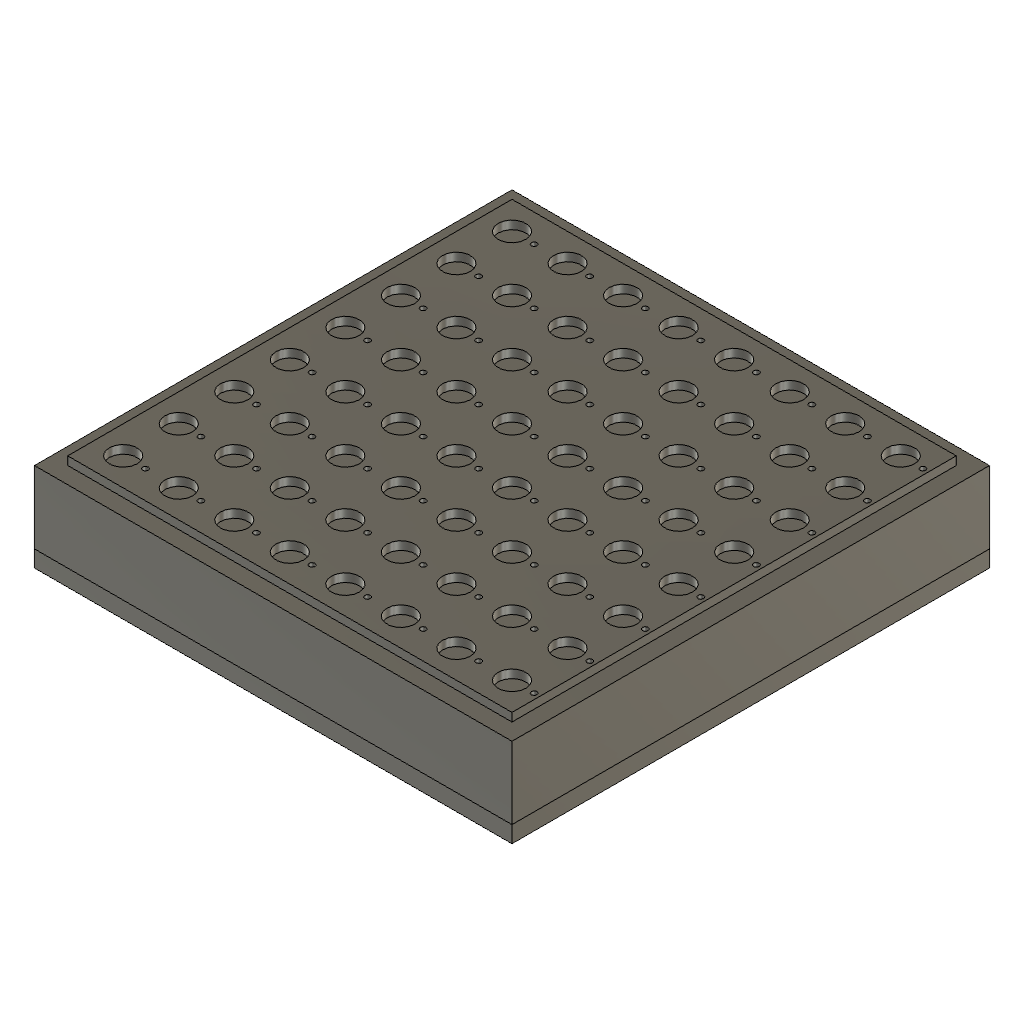
final (Autodesk Fusion 360 design; units mm, degrees)
part number: 2026-11-04-18-17-43-096
part number: 2026-11-04-18-49-42-338
part number: 2026-11-04-20-15-32-787
Autodesk Fusion 360 part; units mm, degrees
sketch "Sketch1" plane through (0, 0, 0) normal (0, 0, 1) x (1, 0, 0)
  circle A0 centre (5, -5) radius 2.5
  circle A1 centre (15, -5) radius 2.5
  circle A2 centre (25, -5) radius 2.5
  circle A3 centre (35, -5) radius 2.5
  circle A4 centre (45, -5) radius 2.5
  circle A5 centre (55, -5) radius 2.5
  circle A6 centre (65, -5) radius 2.5
  circle A7 centre (75, -5) radius 2.5
  circle A8 centre (5, -15) radius 2.5
  circle A9 centre (15, -15) radius 2.5
  circle A10 centre (25, -15) radius 2.5
  circle A11 centre (35, -15) radius 2.5
  circle A12 centre (45, -15) radius 2.5
  circle A13 centre (55, -15) radius 2.5
  circle A14 centre (65, -15) radius 2.5
  circle A15 centre (75, -15) radius 2.5
  circle A16 centre (5, -25) radius 2.5
  circle A17 centre (15, -25) radius 2.5
  circle A18 centre (25, -25) radius 2.5
  circle A19 centre (35, -25) radius 2.5
  circle A20 centre (45, -25) radius 2.5
  circle A21 centre (55, -25) radius 2.5
  circle A22 centre (65, -25) radius 2.5
  circle A23 centre (75, -25) radius 2.5
  circle A24 centre (5, -35) radius 2.5
  circle A25 centre (15, -35) radius 2.5
  circle A26 centre (25, -35) radius 2.5
  circle A27 centre (35, -35) radius 2.5
  circle A28 centre (45, -35) radius 2.5
  circle A29 centre (55, -35) radius 2.5
  circle A30 centre (65, -35) radius 2.5
  circle A31 centre (75, -35) radius 2.5
  circle A32 centre (5, -45) radius 2.5
  circle A33 centre (15, -45) radius 2.5
  circle A34 centre (25, -45) radius 2.5
  circle A35 centre (35, -45) radius 2.5
  circle A36 centre (45, -45) radius 2.5
  circle A37 centre (55, -45) radius 2.5
  circle A38 centre (65, -45) radius 2.5
  circle A39 centre (75, -45) radius 2.5
  circle A40 centre (5, -55) radius 2.5
  circle A41 centre (15, -55) radius 2.5
  circle A42 centre (25, -55) radius 2.5
  circle A43 centre (35, -55) radius 2.5
  circle A44 centre (45, -55) radius 2.5
  circle A45 centre (55, -55) radius 2.5
  circle A46 centre (65, -55) radius 2.5
  circle A47 centre (75, -55) radius 2.5
  circle A48 centre (5, -65) radius 2.5
  circle A49 centre (15, -65) radius 2.5
  circle A50 centre (25, -65) radius 2.5
  circle A51 centre (35, -65) radius 2.5
  circle A52 centre (45, -65) radius 2.5
  circle A53 centre (55, -65) radius 2.5
  circle A54 centre (65, -65) radius 2.5
  circle A55 centre (75, -65) radius 2.5
  circle A56 centre (5, -75) radius 2.5
  circle A57 centre (15, -75) radius 2.5
  circle A58 centre (25, -75) radius 2.5
  circle A59 centre (35, -75) radius 2.5
  circle A60 centre (45, -75) radius 2.5
  circle A61 centre (55, -75) radius 2.5
  circle A62 centre (65, -75) radius 2.5
  circle A63 centre (75, -75) radius 2.5
  line L0 (80, -75) -> (80, -80)
  line L1 (80, -80) -> (75, -80)
  line L2 (80, -80) -> (0, -80)
  line L3 (0, -80) -> (0, 0)
  line L4 (0, 0) -> (80, 0)
  line L5 (80, 0) -> (80, -80)
  dimension "d3" = 5
  dimension "d8" = 70
  dimension "d9" = -70
  dimension "d10" = 5
  dimension "d11" = 5
  constraint vertical L0
  constraint horizontal L1
  constraint horizontal L2
  constraint vertical L3
  constraint horizontal L4
  constraint vertical L5
  constraint coincident L3.end L4.start
  measures "d3" diameter of A0
  measures "d10" distance of A63.centre L0.start
  measures "d11" distance of A63.centre L1.end
extrude "Extrude1" add sketch "Sketch1" against normal blind 3 makes body 1
extrude "Extrude2" cut 1 faces at (18.9442, -68.9001, -3) along direction (0, 0, 1) blind 1.5 on bodies 1 bodies 1
sketch "Sketch1 (2)" plane through (0, 0, -1.5) normal (0, 0, -1) x (1, 0, 0) in component "mainbody "
  circle A0 centre (15, 15) radius 2.5
  circle A1 centre (35, 65) radius 2.5
  circle A2 centre (55, 55) radius 2.5
  circle A3 centre (35, 35) radius 2.5
  circle A4 centre (75, 25) radius 2.5
  circle A5 centre (55, 25) radius 2.5
  circle A6 centre (65, 15) radius 2.5
  circle A7 centre (25, 55) radius 2.5
  circle A8 centre (15, 55) radius 2.5
  circle A9 centre (75, 45) radius 2.5
  circle A10 centre (15, 25) radius 2.5
  circle A11 centre (5, 75) radius 2.5
  circle A12 centre (65, 65) radius 2.5
  circle A13 centre (25, 75) radius 2.5
  circle A14 centre (25, 65) radius 2.5
  circle A15 centre (55, 75) radius 2.5
  circle A16 centre (75, 75) radius 2.5
  circle A17 centre (65, 35) radius 2.5
  circle A18 centre (25, 5) radius 2.5
  circle A19 centre (15, 35) radius 2.5
  circle A20 centre (45, 15) radius 2.5
  circle A21 centre (35, 5) radius 2.5
  circle A22 centre (35, 15) radius 2.5
  circle A23 centre (15, 5) radius 2.5
  circle A24 centre (65, 45) radius 2.5
  circle A25 centre (5, 45) radius 2.5
  circle A26 centre (75, 65) radius 2.5
  circle A27 centre (55, 35) radius 2.5
  line L0 (0, 0) -> (80, 0)
  line L1 (80, 0) -> (80, 80)
  line L2 (80, 80) -> (0, 80)
  line L3 (0, 80) -> (0, 0)
  circle A28 centre (65, 5) radius 2.5
  circle A29 centre (25, 15) radius 2.5
  circle A30 centre (15, 45) radius 2.5
  circle A31 centre (35, 25) radius 2.5
  circle A32 centre (45, 5) radius 2.5
  circle A33 centre (55, 15) radius 2.5
  circle A34 centre (65, 25) radius 2.5
  circle A35 centre (45, 45) radius 2.5
  circle A36 centre (5, 15) radius 2.5
  circle A37 centre (75, 55) radius 2.5
  circle A38 centre (75, 15) radius 2.5
  circle A39 centre (25, 25) radius 2.5
  circle A40 centre (25, 45) radius 2.5
  circle A41 centre (5, 55) radius 2.5
  circle A42 centre (25, 35) radius 2.5
  circle A43 centre (55, 45) radius 2.5
  circle A44 centre (45, 25) radius 2.5
  circle A45 centre (35, 75) radius 2.5
  circle A46 centre (15, 65) radius 2.5
  circle A47 centre (45, 65) radius 2.5
  circle A48 centre (5, 65) radius 2.5
  circle A49 centre (65, 75) radius 2.5
  circle A50 centre (15, 75) radius 2.5
  circle A51 centre (35, 55) radius 2.5
  circle A52 centre (75, 5) radius 2.5
  circle A53 centre (55, 5) radius 2.5
  circle A54 centre (5, 25) radius 2.5
  circle A55 centre (55, 65) radius 2.5
  circle A56 centre (5, 5) radius 2.5
  circle A57 centre (75, 35) radius 2.5
  circle A58 centre (45, 75) radius 2.5
  circle A59 centre (45, 35) radius 2.5
  circle A60 centre (5, 35) radius 2.5
  circle A61 centre (65, 55) radius 2.5
  circle A62 centre (45, 55) radius 2.5
  circle A63 centre (35, 45) radius 2.5
  line L4 (0, 0) -> (0, 80)
  circle A64 centre (5, 65) radius 2.5
  circle A65 centre (5, 75) radius 2.5
  circle A66 centre (15, 75) radius 2.5
  line L5 (0, 80) -> (80, 80)
  circle A67 centre (25, 75) radius 2.5
  circle A68 centre (35, 75) radius 2.5
  circle A69 centre (45, 75) radius 2.5
  circle A70 centre (55, 75) radius 2.5
  circle A71 centre (65, 75) radius 2.5
  circle A72 centre (75, 75) radius 2.5
  line L6 (80, 80) -> (80, 0)
  circle A73 centre (75, 65) radius 2.5
  circle A74 centre (65, 65) radius 2.5
  circle A75 centre (55, 65) radius 2.5
  circle A76 centre (45, 65) radius 2.5
  circle A77 centre (35, 65) radius 2.5
  circle A78 centre (25, 65) radius 2.5
  circle A79 centre (15, 65) radius 2.5
  circle A80 centre (5, 55) radius 2.5
  circle A81 centre (15, 55) radius 2.5
  circle A82 centre (25, 55) radius 2.5
  circle A83 centre (35, 55) radius 2.5
  circle A84 centre (45, 55) radius 2.5
  circle A85 centre (55, 55) radius 2.5
  circle A86 centre (65, 55) radius 2.5
  circle A87 centre (75, 55) radius 2.5
  circle A88 centre (75, 45) radius 2.5
  circle A89 centre (65, 45) radius 2.5
  circle A90 centre (55, 45) radius 2.5
  circle A91 centre (45, 45) radius 2.5
  circle A92 centre (35, 45) radius 2.5
  circle A93 centre (25, 45) radius 2.5
  circle A94 centre (15, 45) radius 2.5
  circle A95 centre (5, 45) radius 2.5
  circle A96 centre (5, 35) radius 2.5
  circle A97 centre (15, 35) radius 2.5
  circle A98 centre (25, 35) radius 2.5
  circle A99 centre (35, 35) radius 2.5
  circle A100 centre (45, 35) radius 2.5
  circle A101 centre (55, 35) radius 2.5
  circle A102 centre (65, 35) radius 2.5
  circle A103 centre (75, 35) radius 2.5
  circle A104 centre (75, 25) radius 2.5
  circle A105 centre (65, 25) radius 2.5
  circle A106 centre (55, 25) radius 2.5
  circle A107 centre (45, 25) radius 2.5
  circle A108 centre (35, 25) radius 2.5
  circle A109 centre (25, 25) radius 2.5
  circle A110 centre (15, 25) radius 2.5
  circle A111 centre (5, 25) radius 2.5
  circle A112 centre (5, 15) radius 2.5
  circle A113 centre (5, 5) radius 2.5
  line L7 (80, 0) -> (0, 0)
  circle A114 centre (15, 5) radius 2.5
  circle A115 centre (15, 15) radius 2.5
  circle A116 centre (25, 15) radius 2.5
  circle A117 centre (25, 5) radius 2.5
  circle A118 centre (35, 5) radius 2.5
  circle A119 centre (35, 15) radius 2.5
  circle A120 centre (45, 15) radius 2.5
  circle A121 centre (45, 5) radius 2.5
  circle A122 centre (55, 5) radius 2.5
  circle A123 centre (65, 5) radius 2.5
  circle A124 centre (75, 5) radius 2.5
  circle A125 centre (75, 15) radius 2.5
  circle A126 centre (65, 15) radius 2.5
  circle A127 centre (9, 75) radius 0.5
  line L8 (15, 75) -> (19, 75)
  circle A128 centre (19, 75) radius 0.5
  circle A129 centre (29, 75) radius 0.5
  circle A130 centre (39, 75) radius 0.5
  circle A131 centre (49, 75) radius 0.5
  circle A132 centre (59, 75) radius 0.5
  circle A133 centre (69, 75) radius 0.5
  circle A134 centre (79, 75) radius 0.5
  circle A135 centre (9, 65) radius 0.5
  circle A136 centre (19, 65) radius 0.5
  circle A137 centre (29, 65) radius 0.5
  circle A138 centre (39, 65) radius 0.5
  circle A139 centre (49, 65) radius 0.5
  circle A140 centre (59, 65) radius 0.5
  circle A141 centre (69, 65) radius 0.5
  circle A142 centre (79, 65) radius 0.5
  circle A143 centre (9, 55) radius 0.5
  circle A144 centre (19, 55) radius 0.5
  circle A145 centre (29, 55) radius 0.5
  circle A146 centre (39, 55) radius 0.5
  circle A147 centre (49, 55) radius 0.5
  circle A148 centre (59, 55) radius 0.5
  circle A149 centre (69, 55) radius 0.5
  circle A150 centre (79, 55) radius 0.5
  circle A151 centre (9, 45) radius 0.5
  circle A152 centre (19, 45) radius 0.5
  circle A153 centre (29, 45) radius 0.5
  circle A154 centre (39, 45) radius 0.5
  circle A155 centre (49, 45) radius 0.5
  circle A156 centre (59, 45) radius 0.5
  circle A157 centre (69, 45) radius 0.5
  circle A158 centre (79, 45) radius 0.5
  circle A159 centre (9, 35) radius 0.5
  circle A160 centre (19, 35) radius 0.5
  circle A161 centre (29, 35) radius 0.5
  circle A162 centre (39, 35) radius 0.5
  circle A163 centre (49, 35) radius 0.5
  circle A164 centre (59, 35) radius 0.5
  circle A165 centre (69, 35) radius 0.5
  circle A166 centre (79, 35) radius 0.5
  circle A167 centre (9, 25) radius 0.5
  circle A168 centre (19, 25) radius 0.5
  circle A169 centre (29, 25) radius 0.5
  circle A170 centre (39, 25) radius 0.5
  circle A171 centre (49, 25) radius 0.5
  circle A172 centre (59, 25) radius 0.5
  circle A173 centre (69, 25) radius 0.5
  circle A174 centre (79, 25) radius 0.5
  circle A175 centre (9, 15) radius 0.5
  circle A176 centre (19, 15) radius 0.5
  circle A177 centre (29, 15) radius 0.5
  circle A178 centre (39, 15) radius 0.5
  circle A179 centre (49, 15) radius 0.5
  circle A180 centre (59, 15) radius 0.5
  circle A181 centre (69, 15) radius 0.5
  circle A182 centre (79, 15) radius 0.5
  circle A183 centre (9, 5) radius 0.5
  circle A184 centre (19, 5) radius 0.5
  circle A185 centre (29, 5) radius 0.5
  circle A186 centre (39, 5) radius 0.5
  circle A187 centre (49, 5) radius 0.5
  circle A188 centre (59, 5) radius 0.5
  circle A189 centre (69, 5) radius 0.5
  circle A190 centre (79, 5) radius 0.5
  point P0 (72.5, 5)
  dimension "d20" = 4
  dimension "d21" = 1
  dimension "d22" = 4
  dimension "d26" = 70
  dimension "d27" = -70
  constraint coincident A50.centre A66.centre
  constraint horizontal L8
  measures "d20" distance of A11.centre A127.centre
  measures "d21" diameter of A127
  measures "d22" distance of A50.centre L8.end
extrude "Extrude1'" add sketch "Sketch1 (2)" along normal blind 3 separate body contours A0 A115 | A1 A77 | A2 A85 | A3 A99 | A4 A104 | A5 A106 | A6 A126 | A7 A82 | A8 A81 | A9 A88 | A10 A110 | A11 A65 | A12 A74 | A13 A67 | A14 A78 | A15 A70 | A16 A72 | A17 A102 | A18 A117 | A19 A97 | A20 A120 | A21 A118 | A22 A119 | A23 A114 | A24 A89 | A25 A95 | A26 A73 | A27 A101 | L0 L1 L2 L3 L4 L5 L6 L7 | A28 A123 | A29 A116 | A30 A94 | A31 A108 | A32 A121 | A33 | A34 A105 | A35 A91 | A36 A112 | A37 A87 | A38 A125 | A39 A109 | A40 A93 | A41 A80 | A42 A98 | A43 A90 | A44 A107 | A45 A68 | A46 A79 | A47 A76 | A48 A64 | A49 A71 | A50 A66 | A51 A83 | A52 A124 | A53 A122 | A54 A111 | A55 A75 | A56 A113 | A57 A103 | A58 A69 | A59 A100 | A60 A96 | A61 A86 | A62 A84 | A63 A92 makes body 2 in component "mainbody "
sketch "Sketch2" plane through (0, 0, 0) normal (0, 0, 1) x (-1, 0, 0)
  circle A0 centre (-15, 15) radius 2.5
  circle A1 centre (-35, 65) radius 2.5
  circle A2 centre (-55, 55) radius 2.5
  circle A3 centre (-35, 35) radius 2.5
  circle A4 centre (-75, 25) radius 2.5
  circle A5 centre (-55, 25) radius 2.5
  circle A6 centre (-65, 15) radius 2.5
  circle A7 centre (-25, 55) radius 2.5
  circle A8 centre (-15, 55) radius 2.5
  circle A9 centre (-75, 45) radius 2.5
  circle A10 centre (-15, 25) radius 2.5
  circle A11 centre (-5, 75) radius 2.5
  circle A12 centre (-65, 65) radius 2.5
  circle A13 centre (-25, 75) radius 2.5
  circle A14 centre (-25, 65) radius 2.5
  circle A15 centre (-55, 75) radius 2.5
  circle A16 centre (-75, 75) radius 2.5
  circle A17 centre (-65, 35) radius 2.5
  circle A18 centre (-25, 5) radius 2.5
  circle A19 centre (-15, 35) radius 2.5
  circle A20 centre (-45, 15) radius 2.5
  circle A21 centre (-35, 5) radius 2.5
  circle A22 centre (-35, 15) radius 2.5
  circle A23 centre (-15, 5) radius 2.5
  circle A24 centre (-65, 45) radius 2.5
  circle A25 centre (-5, 45) radius 2.5
  circle A26 centre (-75, 65) radius 2.5
  circle A27 centre (-55, 35) radius 2.5
  line L0 (-80, 0) -> (0, 0)
  line L1 (0, 0) -> (0, 80)
  line L2 (0, 80) -> (-80, 80)
  line L3 (-80, 80) -> (-80, 0)
  circle A28 centre (-65, 5) radius 2.5
  circle A29 centre (-25, 15) radius 2.5
  circle A30 centre (-15, 45) radius 2.5
  circle A31 centre (-35, 25) radius 2.5
  circle A32 centre (-45, 5) radius 2.5
  circle A33 centre (-55, 15) radius 2.5
  circle A34 centre (-65, 25) radius 2.5
  circle A35 centre (-45, 45) radius 2.5
  circle A36 centre (-5, 15) radius 2.5
  circle A37 centre (-75, 55) radius 2.5
  circle A38 centre (-75, 15) radius 2.5
  circle A39 centre (-25, 25) radius 2.5
  circle A40 centre (-25, 45) radius 2.5
  circle A41 centre (-5, 55) radius 2.5
  circle A42 centre (-25, 35) radius 2.5
  circle A43 centre (-55, 45) radius 2.5
  circle A44 centre (-45, 25) radius 2.5
  circle A45 centre (-35, 75) radius 2.5
  circle A46 centre (-15, 65) radius 2.5
  circle A47 centre (-45, 65) radius 2.5
  circle A48 centre (-5, 65) radius 2.5
  circle A49 centre (-65, 75) radius 2.5
  circle A50 centre (-15, 75) radius 2.5
  circle A51 centre (-35, 55) radius 2.5
  circle A52 centre (-75, 5) radius 2.5
  circle A53 centre (-55, 5) radius 2.5
  circle A54 centre (-5, 25) radius 2.5
  circle A55 centre (-55, 65) radius 2.5
  circle A56 centre (-5, 5) radius 2.5
  circle A57 centre (-75, 35) radius 2.5
  circle A58 centre (-45, 75) radius 2.5
  circle A59 centre (-45, 35) radius 2.5
  circle A60 centre (-5, 35) radius 2.5
  circle A61 centre (-65, 55) radius 2.5
  circle A62 centre (-45, 55) radius 2.5
  circle A63 centre (-35, 45) radius 2.5
  circle A64 centre (-9, 5) radius 0.5
  circle A65 centre (-9, 25) radius 0.5
  circle A66 centre (-9, 35) radius 0.5
  circle A67 centre (-9, 45) radius 0.5
  circle A68 centre (-9, 55) radius 0.5
  circle A69 centre (-9, 65) radius 0.5
  circle A70 centre (-9, 75) radius 0.5
  circle A71 centre (-9, 15) radius 0.5
  circle A72 centre (-19, 5) radius 0.5
  circle A73 centre (-19, 15) radius 0.5
  circle A74 centre (-19, 25) radius 0.5
  circle A75 centre (-19, 35) radius 0.5
  circle A76 centre (-19, 45) radius 0.5
  circle A77 centre (-19, 55) radius 0.5
  circle A78 centre (-19, 65) radius 0.5
  circle A79 centre (-19, 75) radius 0.5
  circle A80 centre (-29, 75) radius 0.5
  circle A81 centre (-29, 65) radius 0.5
  circle A82 centre (-29, 55) radius 0.5
  circle A83 centre (-29, 45) radius 0.5
  circle A84 centre (-29, 35) radius 0.5
  circle A85 centre (-29, 25) radius 0.5
  circle A86 centre (-29, 15) radius 0.5
  circle A87 centre (-29, 5) radius 0.5
  circle A88 centre (-39, 5) radius 0.5
  circle A89 centre (-39, 15) radius 0.5
  circle A90 centre (-39, 25) radius 0.5
  circle A91 centre (-39, 35) radius 0.5
  circle A92 centre (-39, 45) radius 0.5
  circle A93 centre (-39, 55) radius 0.5
  circle A94 centre (-39, 65) radius 0.5
  circle A95 centre (-39, 75) radius 0.5
  circle A96 centre (-49, 75) radius 0.5
  circle A97 centre (-49, 65) radius 0.5
  circle A98 centre (-49, 55) radius 0.5
  circle A99 centre (-49, 45) radius 0.5
  circle A100 centre (-49, 35) radius 0.5
  circle A101 centre (-49, 25) radius 0.5
  circle A102 centre (-49, 15) radius 0.5
  circle A103 centre (-49, 5) radius 0.5
  circle A104 centre (-59, 5) radius 0.5
  circle A105 centre (-59, 15) radius 0.5
  circle A106 centre (-59, 25) radius 0.5
  circle A107 centre (-59, 35) radius 0.5
  circle A108 centre (-59, 45) radius 0.5
  circle A109 centre (-59, 55) radius 0.5
  circle A110 centre (-59, 65) radius 0.5
  circle A111 centre (-59, 75) radius 0.5
  circle A112 centre (-69, 75) radius 0.5
  circle A113 centre (-79, 75) radius 0.5
  circle A114 centre (-79, 65) radius 0.5
  circle A115 centre (-69, 65) radius 0.5
  circle A116 centre (-69, 55) radius 0.5
  circle A117 centre (-79, 55) radius 0.5
  circle A118 centre (-69, 45) radius 0.5
  circle A119 centre (-79, 45) radius 0.5
  circle A120 centre (-69, 35) radius 0.5
  circle A121 centre (-69, 25) radius 0.5
  circle A122 centre (-79, 25) radius 0.5
  circle A123 centre (-79, 35) radius 0.5
  circle A124 centre (-69, 15) radius 0.5
  circle A125 centre (-79, 15) radius 0.5
  circle A126 centre (-69, 5) radius 0.5
  circle A127 centre (-79, 5) radius 0.5
extrude "Extrude3" cut sketch "Sketch2" against normal blind 10 contours A64 | A65 | A66 | A67 | A68 | A69 | A70 | A71 | A72 | A73 | A74 | A75 | A76 | A77 | A78 | A79 | A80 | A81 | A82 | A83 | A84 | A85 | A86 | A87 | A88 | A89 | A90 | A91 | A92 | A93 | A94 | A95 | A96 | A97 | A98 | A99 | A100 | A101 | A102 | A103 | A104 | A105 | A106 | A107 | A108 | A109 | A110 | A111 | A112 | A113 | A114 | A115 | A116 | A117 | A118 | A119 | A120 | A121 | A122 | A123 | A124 | A125 | A126 | A127 bodies 1
sketch "Sketch3" plane through (0, 0, -4.5) normal (0, 0, -1) x (1, 0, 0)
  circle A0 centre (69, 5) radius 0.5
  circle A1 centre (59, 25) radius 0.5
  circle A2 centre (39, 65) radius 0.5
  circle A3 centre (39, 75) radius 0.5
  circle A4 centre (29, 55) radius 0.5
  circle A5 centre (39, 55) radius 0.5
  circle A6 centre (59, 75) radius 0.5
  circle A7 centre (59, 55) radius 0.5
  circle A8 centre (29, 75) radius 0.5
  circle A9 centre (59, 15) radius 0.5
  circle A10 centre (9, 65) radius 0.5
  circle A11 centre (59, 45) radius 0.5
  circle A12 centre (29, 65) radius 0.5
  circle A13 centre (79, 15) radius 0.5
  circle A14 centre (79, 75) radius 0.5
  circle A15 centre (49, 75) radius 0.5
  circle A16 centre (19, 35) radius 0.5
  circle A17 centre (59, 65) radius 0.5
  circle A18 centre (29, 45) radius 0.5
  circle A19 centre (79, 45) radius 0.5
  circle A20 centre (79, 55) radius 0.5
  circle A21 centre (9, 25) radius 0.5
  circle A22 centre (29, 25) radius 0.5
  circle A23 centre (79, 25) radius 0.5
  circle A24 centre (9, 5) radius 0.5
  circle A25 centre (19, 15) radius 0.5
  circle A26 centre (19, 75) radius 0.5
  circle A27 centre (19, 5) radius 0.5
  line L0 (80, 0) -> (80, 80)
  line L1 (80, 80) -> (0, 80)
  line L2 (0, 80) -> (0, 0)
  line L3 (0, 0) -> (80, 0)
  circle A28 centre (49, 55) radius 0.5
  circle A29 centre (69, 15) radius 0.5
  circle A30 centre (19, 25) radius 0.5
  circle A31 centre (49, 25) radius 0.5
  circle A32 centre (79, 35) radius 0.5
  circle A33 centre (29, 5) radius 0.5
  circle A34 centre (49, 15) radius 0.5
  circle A35 centre (79, 5) radius 0.5
  circle A36 centre (69, 25) radius 0.5
  circle A37 centre (39, 15) radius 0.5
  circle A38 centre (9, 15) radius 0.5
  circle A39 centre (19, 65) radius 0.5
  circle A40 centre (9, 75) radius 0.5
  circle A41 centre (39, 5) radius 0.5
  circle A42 centre (59, 5) radius 0.5
  circle A43 centre (79, 65) radius 0.5
  circle A44 centre (29, 35) radius 0.5
  circle A45 centre (69, 75) radius 0.5
  circle A46 centre (69, 55) radius 0.5
  circle A47 centre (69, 65) radius 0.5
  circle A48 centre (9, 55) radius 0.5
  circle A49 centre (9, 35) radius 0.5
  circle A50 centre (69, 45) radius 0.5
  circle A51 centre (59, 35) radius 0.5
  circle A52 centre (9, 45) radius 0.5
  circle A53 centre (39, 35) radius 0.5
  circle A54 centre (49, 45) radius 0.5
  circle A55 centre (49, 65) radius 0.5
  circle A56 centre (39, 45) radius 0.5
  circle A57 centre (19, 45) radius 0.5
  circle A58 centre (49, 35) radius 0.5
  circle A59 centre (69, 35) radius 0.5
  circle A60 centre (19, 55) radius 0.5
  circle A61 centre (29, 15) radius 0.5
  circle A62 centre (49, 5) radius 0.5
  circle A63 centre (39, 25) radius 0.5
  line L4 (-3, -3) -> (83, -3)
  line L5 (83, -3) -> (83, 83)
  line L6 (83, 83) -> (-3, 83)
  line L7 (-3, 83) -> (-3, -3)
  dimension "d32" = 3
extrude "Extrude2'" add sketch "Sketch3" against normal blind 3 contours L4 L5 L6 L7 bodies 2 in component "mainbody "
sketch "Sketch4" plane through (0, 0, -4.5) normal (0, 0, -1) x (1, 0, 0)
  line L0 (-3, 83) -> (-3, -3)
  line L1 (-3, -3) -> (83, -3)
  line L2 (83, -3) -> (83, 83)
  line L3 (83, 83) -> (-3, 83)
  circle A0 centre (69, 5) radius 0.5
  circle A1 centre (59, 25) radius 0.5
  circle A2 centre (39, 65) radius 0.5
  circle A3 centre (39, 75) radius 0.5
  circle A4 centre (29, 55) radius 0.5
  circle A5 centre (39, 55) radius 0.5
  circle A6 centre (59, 75) radius 0.5
  circle A7 centre (59, 55) radius 0.5
  circle A8 centre (29, 75) radius 0.5
  circle A9 centre (59, 15) radius 0.5
  circle A10 centre (9, 65) radius 0.5
  circle A11 centre (59, 45) radius 0.5
  circle A12 centre (29, 65) radius 0.5
  circle A13 centre (79, 15) radius 0.5
  circle A14 centre (79, 75) radius 0.5
  circle A15 centre (49, 75) radius 0.5
  circle A16 centre (19, 35) radius 0.5
  circle A17 centre (59, 65) radius 0.5
  circle A18 centre (29, 45) radius 0.5
  circle A19 centre (79, 45) radius 0.5
  circle A20 centre (79, 55) radius 0.5
  circle A21 centre (9, 25) radius 0.5
  circle A22 centre (29, 25) radius 0.5
  circle A23 centre (79, 25) radius 0.5
  circle A24 centre (9, 5) radius 0.5
  circle A25 centre (19, 15) radius 0.5
  circle A26 centre (19, 75) radius 0.5
  circle A27 centre (19, 5) radius 0.5
  circle A28 centre (49, 55) radius 0.5
  circle A29 centre (69, 15) radius 0.5
  circle A30 centre (19, 25) radius 0.5
  circle A31 centre (49, 25) radius 0.5
  circle A32 centre (79, 35) radius 0.5
  circle A33 centre (29, 5) radius 0.5
  circle A34 centre (49, 15) radius 0.5
  circle A35 centre (79, 5) radius 0.5
  circle A36 centre (69, 25) radius 0.5
  circle A37 centre (39, 15) radius 0.5
  circle A38 centre (9, 15) radius 0.5
  circle A39 centre (19, 65) radius 0.5
  circle A40 centre (9, 75) radius 0.5
  circle A41 centre (39, 5) radius 0.5
  circle A42 centre (59, 5) radius 0.5
  circle A43 centre (79, 65) radius 0.5
  circle A44 centre (29, 35) radius 0.5
  circle A45 centre (69, 75) radius 0.5
  circle A46 centre (69, 55) radius 0.5
  circle A47 centre (69, 65) radius 0.5
  circle A48 centre (9, 55) radius 0.5
  circle A49 centre (9, 35) radius 0.5
  circle A50 centre (69, 45) radius 0.5
  circle A51 centre (59, 35) radius 0.5
  circle A52 centre (9, 45) radius 0.5
  circle A53 centre (39, 35) radius 0.5
  circle A54 centre (49, 45) radius 0.5
  circle A55 centre (49, 65) radius 0.5
  circle A56 centre (39, 45) radius 0.5
  circle A57 centre (19, 45) radius 0.5
  circle A58 centre (49, 35) radius 0.5
  circle A59 centre (69, 35) radius 0.5
  circle A60 centre (19, 55) radius 0.5
  circle A61 centre (29, 15) radius 0.5
  circle A62 centre (49, 5) radius 0.5
  circle A63 centre (39, 25) radius 0.5
  line L4 (0, 80) -> (0, 0)
  line L5 (0, 80) -> (80, 80)
  line L6 (0, 0) -> (80, 0)
  line L7 (80, 80) -> (80, 0)
extrude "Extrude3'" add sketch "Sketch4" along normal blind 7 contours L0 L1 L2 L3 bodies 2 in component "mainbody "
sketch "Sketch5" plane through (0, 0, -11.5) normal (0, 0, -1) x (1, 0, 0)
  line L0 (0, 0) -> (0, 80)
  line L1 (0, 80) -> (80, 80)
  line L2 (80, 80) -> (80, 0)
  line L3 (80, 0) -> (0, 0)
  line L4 (83, 83) -> (-3, 83)
  line L5 (-3, 83) -> (-3, -3)
  line L6 (-3, -3) -> (83, -3)
  line L7 (83, -3) -> (83, 83)
  line L8 (0, 0) -> (5, 0)
  line L9 (5, 0) -> (5, 5)
  line L10 (5, 5) -> (0, 5)
  line L11 (80, 0) -> (75, 0)
  line L12 (75, 0) -> (75, 5)
  line L13 (75, 5) -> (80, 5)
  line L14 (80, 0) -> (80, 5)
  line L15 (80, 80) -> (80, 75)
  line L16 (80, 75) -> (75, 75)
  line L17 (75, 75) -> (75, 80)
  line L18 (80, 80) -> (75, 80)
  line L19 (0, 80) -> (5, 80)
  line L20 (5, 80) -> (5, 75)
  line L21 (5, 75) -> (0, 75)
  line L22 (0, 75) -> (0, 80)
  dimension "d37" = 5
  dimension "d38" = 5
  dimension "d39" = 5
  dimension "d40" = 5
  dimension "d41" = 5
  dimension "d42" = 5
  dimension "d43" = 5
  dimension "d44" = 5
  constraint coincident L0.start L3.end
  constraint perpendicular L0 L8
  constraint perpendicular L8 L9
  constraint coincident L0 L10.end
  constraint perpendicular L0 L10
  constraint coincident L2.end L3.start
  constraint perpendicular L2 L11
  constraint perpendicular L3 L12
  constraint coincident L2 L13.end
  constraint perpendicular L2 L13
  constraint coincident L1.end L2.start
  constraint perpendicular L1 L15
  constraint perpendicular L2 L16
  constraint coincident L1 L17.end
  constraint perpendicular L1 L17
  constraint coincident L0.end L1.start
  constraint perpendicular L0 L19
  constraint perpendicular L19 L20
  constraint coincident L0 L21.end
  constraint perpendicular L0 L21
  measures "d37" distance of L0.start L8.end
  measures "d38" distance of L8.end L9.end
  measures "d39" distance of L2.end L11.end
  measures "d40" distance of L11.end L12.end
  measures "d41" distance of L1.end L15.end
  measures "d42" distance of L15.end L16.end
  measures "d43" distance of L0.end L19.end
  measures "d44" distance of L19.end L20.end
extrude "Extrude4" add sketch "Sketch5" against normal blind 5 contours L0 L3 L8 L9 L10 | L0 L1 L19 L20 L21 L22 | L2 L3 L11 L12 L13 L14 | L1 L2 L15 L16 L17 L18 bodies 2 in component "mainbody "
sketch "Sketch6" plane through (0, 0, -11.5) normal (0, 0, -1) x (1, 0, 0)
  line L0 (0, 5) -> (0, 75)
  line L1 (0, 75) -> (5, 75)
  line L2 (5, 75) -> (5, 80)
  line L3 (5, 80) -> (75, 80)
  line L4 (75, 80) -> (75, 75)
  line L5 (75, 75) -> (80, 75)
  line L6 (80, 75) -> (80, 5)
  line L7 (80, 5) -> (75, 5)
  line L8 (75, 5) -> (75, 0)
  line L9 (75, 0) -> (5, 0)
  line L10 (5, 0) -> (5, 5)
  line L11 (5, 5) -> (0, 5)
  line L12 (83, 83) -> (-3, 83)
  line L13 (-3, 83) -> (-3, -3)
  line L14 (-3, -3) -> (83, -3)
  line L15 (83, -3) -> (83, 83)
  circle A0 centre (2.5, 2.5) radius 2.05
  circle A1 centre (77.5, 2.5) radius 2.05
  circle A2 centre (77.5, 77.5) radius 2.05
  circle A3 centre (2.5, 77.5) radius 2.05
  dimension "d53" = 4.1
  dimension "d54" = 4.1
  dimension "d55" = 4.1
  dimension "d56" = 4.1
  measures "d53" diameter of A0
  measures "d54" diameter of A1
  measures "d55" diameter of A2
  measures "d56" diameter of A3
extrude "Extrude5" add 1 faces at (0.6667, -0.6667, -11.5) along direction (0, 0, -1) blind 3 on bodies 2 bodies 2 in component "mainbody "
sketch "Sketch7" plane through (0, 0, -14.5) normal (0, 0, -1) x (1, 0, 0)
  line L0 (0, 5) -> (0, 75)
  line L1 (0, 75) -> (5, 75)
  line L2 (5, 75) -> (5, 80)
  line L3 (5, 80) -> (75, 80)
  line L4 (75, 80) -> (75, 75)
  line L5 (75, 75) -> (80, 75)
  line L6 (80, 75) -> (80, 5)
  line L7 (80, 5) -> (75, 5)
  line L8 (75, 5) -> (75, 0)
  line L9 (75, 0) -> (5, 0)
  line L10 (5, 0) -> (5, 5)
  line L11 (5, 5) -> (0, 5)
  line L12 (83, 83) -> (-3, 83)
  line L13 (-3, 83) -> (-3, -3)
  line L14 (-3, -3) -> (83, -3)
  line L15 (83, -3) -> (83, 83)
  circle A0 centre (2.5, 2.5) radius 2.05
  circle A1 centre (2.5, 77.5) radius 2.05
  circle A2 centre (77.5, 77.5) radius 2.05
  circle A3 centre (77.5, 2.5) radius 2.05
extrude "Extrude6" cut sketch "Sketch7" against normal blind 5 contours A2 bodies 2 in component "mainbody "
extrude "Extrude7" cut sketch "Sketch7" against normal blind 5 contours A0 | A1 | A3 bodies 2 in component "mainbody "
extrude "Extrude8" add 1 faces at (5, -78.3333, -11.8333) along direction (1, 0, 0) blind 1 on bodies 2 bodies 2 in component "mainbody "
extrude "Extrude9" add 1 faces at (4, -75, -11.8333) along direction (0, 1, 0) blind 1 on bodies 2 bodies 2 in component "mainbody "
extrude "Extrude10" add 1 faces at (78.3333, -75, -11.8333) along direction (0, 1, 0) blind 1 on bodies 2 bodies 2 in component "mainbody "
extrude "Extrude11" add 1 faces at (75, -76, -11.8333) along direction (-1, 0, 0) blind 1 on bodies 2 bodies 2 in component "mainbody "
extrude "Extrude12" add 1 faces at (75, -1.6667, -11.8333) along direction (-1, 0, 0) blind 1 on bodies 2 bodies 2 in component "mainbody "
extrude "Extrude13" add 1 faces at (76, -5, -11.8333) along direction (0, -1, 0) blind 1 on bodies 2 bodies 2 in component "mainbody "
extrude "Extrude14" add 1 faces at (3.3333, -5, -11.8333) along direction (0, -1, 0) blind 1 on bodies 2 bodies 2 in component "mainbody "
extrude "Extrude15" add 1 faces at (5, -4, -11.8333) along direction (1, 0, 0) blind 1 on bodies 2 bodies 2 in component "mainbody "
sketch "Sketch8" plane through (0, 0, 0) normal (1, 0, 0) x (0, 1, 0)
  line L0 (-6, -6.5) -> (0, -6.5)
  line L1 (0, -6.5) -> (0, -4.5)
  line L2 (0, -4.5) -> (-80, -4.5)
  line L3 (-80, -4.5) -> (-80, -6.5)
  line L4 (-80, -6.5) -> (-74, -6.5)
  line L5 (-74, -6.5) -> (-74, -14.5)
  line L6 (-74, -14.5) -> (-6, -14.5)
  line L7 (-6, -14.5) -> (-6, -6.5)
  line L8 (-10.0552, -14.5) -> (-10.0552, -9.5)
  line L9 (-10.0552, -9.5) -> (-15.0552, -9.5)
  line L10 (-15.0552, -9.5) -> (-15.0552, -14.5)
  dimension "d79" = 5
  dimension "d80" = 5
  constraint coincident L6 L8.start
  constraint perpendicular L6 L8
  constraint perpendicular L8 L9
  constraint coincident L6 L10.end
  constraint perpendicular L6 L10
  measures "d79" distance of L8.start L8.end
  measures "d80" distance of L8.end L9.end
extrude "Extrude16" cut sketch "Sketch8" against normal blind 24 contours L6 L8 L9 L10 bodies 2 in component "mainbody "
sketch "Sketch9" plane through (0, 0, 0) normal (1, 0, 0) x (0, 1, 0)
  line L0 (-15.0552, -14.5) -> (-15.0552, -9.5)
  line L1 (-15.0552, -9.5) -> (-10.0552, -9.5)
  line L2 (-10.0552, -9.5) -> (-10.0552, -14.5)
  line L3 (-10.0552, -14.5) -> (-6, -14.5)
  line L4 (-6, -14.5) -> (-6, -6.5)
  line L5 (-6, -6.5) -> (0, -6.5)
  line L6 (0, -6.5) -> (0, -4.5)
  line L7 (0, -4.5) -> (-80, -4.5)
  line L8 (-80, -4.5) -> (-80, -6.5)
  line L9 (-80, -6.5) -> (-74, -6.5)
  line L10 (-74, -6.5) -> (-74, -14.5)
  line L11 (-74, -14.5) -> (-15.0552, -14.5)
  line L12 (-31.6905, -14.5) -> (-31.6905, -11.5)
  line L13 (-31.6905, -11.5) -> (-34.6905, -11.5)
  line L14 (-34.6905, -11.5) -> (-34.6905, -14.5)
  dimension "d83" = 3
  dimension "d84" = 3
  constraint coincident L11 L12.start
  constraint perpendicular L11 L12
  constraint perpendicular L12 L13
  constraint coincident L11 L14.end
  constraint perpendicular L11 L14
  measures "d83" distance of L12.start L12.end
  measures "d84" distance of L12.end L13.end
extrude "Extrude17" cut sketch "Sketch9" against normal blind 16 contours L11 L12 L13 L14 bodies 2 in component "mainbody "
sketch "Sketch1 (3)" plane through (0, 0, -14.5) normal (0, 0, -1) x (1, 0, 0) in component "cover"
  line L0 (-3, 34.6905) -> (0, 34.6905)
  line L1 (0, 34.6905) -> (0, 74)
  line L2 (0, 74) -> (6, 74)
  line L3 (6, 74) -> (6, 80)
  line L4 (6, 80) -> (74, 80)
  line L5 (74, 80) -> (74, 74)
  line L6 (74, 74) -> (80, 74)
  line L7 (80, 74) -> (80, 6)
  line L8 (80, 6) -> (74, 6)
  line L9 (74, 6) -> (74, 0)
  line L10 (74, 0) -> (6, 0)
  line L11 (6, 0) -> (6, 6)
  line L12 (6, 6) -> (0, 6)
  line L13 (0, 6) -> (0, 10.0552)
  line L14 (0, 10.0552) -> (-3, 10.0552)
  line L15 (-3, 10.0552) -> (-3, -3)
  line L16 (-3, -3) -> (83, -3)
  line L17 (83, -3) -> (83, 83)
  line L18 (83, 83) -> (-3, 83)
  line L19 (-3, 83) -> (-3, 34.6905)
  circle A0 centre (77.5, 2.5) radius 2.05
  circle A1 centre (2.5, 2.5) radius 2.05
  circle A2 centre (2.5, 77.5) radius 2.05
  circle A3 centre (77.5, 77.5) radius 2.05
  line L20 (-3, -3) -> (-3, 83)
  line L21 (-3, 83) -> (83, 83)
  line L22 (83, 83) -> (83, -3)
  line L23 (83, -3) -> (-3, -3)
  circle A4 centre (2.5, 2.5) radius 2.05
  circle A5 centre (77.5, 2.5) radius 2.05
  circle A6 centre (77.5, 77.5) radius 2.05
  circle A7 centre (2.5, 77.5) radius 2.05
  constraint coincident L15.end L16.start
  constraint coincident L18.end L19.start
  constraint coincident L17.end L18.start
  constraint coincident L16.end L17.start
extrude "Extrude1''" add sketch "Sketch1 (3)" along normal blind 3 separate body contours L0 L1 L2 L3 L4 L5 L6 L7 L8 L9 L10 L11 L12 L13 L14 L15 L16 L17 L18 L19 L20 L21 L22 L23 | L0 L1 L2 L3 L4 L5 L6 L7 L8 L9 L10 L11 L12 L13 L14 L20 | A0 A5 | A1 A4 | A2 A7 | A3 A6 makes body 3 in component "cover"
sketch "Sketch2 (2)" plane through (0, 0, -17.5) normal (0, 0, -1) x (1, 0, 0) in component "cover"
  line L0 (83, -3) -> (83, 83)
  line L1 (83, 83) -> (-3, 83)
  line L2 (-3, 83) -> (-3, -3)
  line L3 (-3, -3) -> (83, -3)
  circle A0 centre (77.5, 2.5) radius 2.05
  circle A1 centre (77.5, 77.5) radius 2.05
  circle A2 centre (2.5, 77.5) radius 2.05
  circle A3 centre (2.5, 2.5) radius 2.05
  circle A4 centre (2.5, 2.5) radius 1.5
  circle A5 centre (77.5, 2.5) radius 1.5
  circle A6 centre (77.5, 77.5) radius 1.5
  circle A7 centre (2.5, 77.5) radius 1.5
  dimension "d89" = 3
  dimension "d90" = 3
  dimension "d91" = 3
  dimension "d92" = 3
  constraint concentric A3 A4
  constraint concentric A0 A5
  constraint concentric A1 A6
  constraint concentric A2 A7
  measures "d89" diameter of A4
  measures "d90" diameter of A5
  measures "d91" diameter of A6
  measures "d92" diameter of A7
extrude "Extrude2''" cut sketch "Sketch2 (2)" against normal blind 8 contours A4 | A5 | A6 | A7 bodies 3 in component "cover"
sketch "Sketch3 (2)" plane through (0, 0, -17.5) normal (0, 0, -1) x (1, 0, 0) in component "cover"
  circle A0 centre (77.5, 77.5) radius 1.5
  circle A1 centre (77.5, 2.5) radius 1.5
  circle A2 centre (2.5, 77.5) radius 1.5
  circle A3 centre (2.5, 2.5) radius 1.5
  line L0 (83, -3) -> (83, 83)
  line L1 (83, 83) -> (-3, 83)
  line L2 (-3, 83) -> (-3, -3)
  line L3 (-3, -3) -> (83, -3)
  circle A4 centre (2.5, 2.5) radius 2.05
  circle A5 centre (2.5, 77.5) radius 2.05
  circle A6 centre (77.5, 77.5) radius 2.05
  circle A7 centre (77.5, 2.5) radius 2.05
extrude "Extrude3''" cut sketch "Sketch3 (2)" against normal blind 1.5 contours A4 | A5 | A6 | A7 bodies 3 in component "cover"
component "mainbody " placed x (1, 0, 0) y (0, 1, 0) z (0, 0, 1) at (0, 0, 0)
component "cover" placed x (1, 0, 0) y (0, 1, 0) z (0, 0, 1) at (0, 0, 0)
